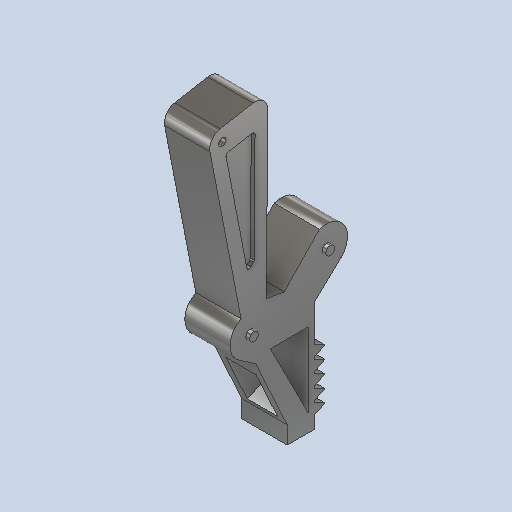
# Autodesk Inventor part: 8
Saved by Autodesk Inventor 2027.1 (Build 311270010, 270A)
## iProperties
Part Number: 8
Material: Allgemein
Document SubType Name: Modellieren
Designer: Asus
Appearance: Chrom - poliert
Author: Asus
Autodesk Inventor part; units mm, degrees
ref_plane "YZ-Ebene" through (0, 0, 0) normal (1, 0, 0) x (0, 1, 0)
ref_plane "XZ-Ebene" through (0, 0, 0) normal (0, 1, 0) x (-1, 0, 0)
ref_plane "XY-Ebene" through (0, 0, 0) normal (0, 0, 1) x (1, 0, 0)
sketch "Skizze1" plane through (0, 0, 0) normal (0, 0, 1) x (1, 0, 0)
  line L0 (0, 0) -> (0, 7)
  line L1 (0, 0) -> (11, 0)
  line L2 (11, 0) -> (11, 44)
  line L3 (0, 7) -> (-12.536, 34.2552)
  line L4 (11, 44) -> (21.3729, 53.8435)
  line L5 (-12.536, 34.2552) -> (-23.2368, 41.6372)
  line L6 (-23.2368, 41.6372) -> (-23.2368, 51.6372)
  line L7 (-23.2368, 51.6372) -> (-18.3337, 52.6169)
  line L8 (-18.3337, 52.6169) -> (-31.6903, 121.3308)
  line L9 (-31.6903, 121.3308) -> (-7.6903, 125.5627)
  line L10 (-7.6903, 125.5627) -> (-8.3099, 54.5654)
  line L11 (-8.3099, 54.5654) -> (-1.2087, 53.3771)
  line L12 (-1.2087, 53.3771) -> (12.8488, 67.8832)
  arc A0 (21.3729, 53.8435) -> (12.8488, 67.8832) centre (15.5884, 59.939) ccw
  dimension "d0" = 7
  dimension "d1" = 11
  dimension "d2" = 44
  dimension "d3" = 30
  dimension "d4" = 155.3
  dimension "d5" = 14.3
  dimension "d6" = 133.5
  dimension "d7" = 149.3
  dimension "d8" = 13
  dimension "d10" = 10
  dimension "d11" = 5
  dimension "d12" = 101.3
  dimension "d13" = 70
  dimension "d14" = 90.3
  dimension "d15" = 24
  dimension "d16" = 89
  dimension "d17" = 71
  dimension "d18" = 79.5
  dimension "d19" = 7.2
  dimension "d20" = 99
  dimension "d21" = 20.2
  dimension "d22" = 124.6
  constraints: 26 end point, 2 point on circle, 2 vertical, 1 centre point, 1 horizontal, 1 perpendicular, 1 tangent
  measures "d0" distance of L0.start L0.end
  measures "d1" distance of L0.start L1.end
  measures "d2" distance of L1.end L2.end
  measures "d3" distance of L0.end L3.end
  measures "d4" angle of L0 L3
  measures "d5" distance of L2.end L4.end
  measures "d6" angle of L2 L4
  measures "d7" angle of L3 L5
  measures "d8" distance of L3.end L5.end
  measures "d10" distance of L5.end L6.end
  measures "d11" distance of L6.end L7.end
  measures "d12" angle of L6 L7
  measures "d13" distance of L7.end L8.end
  measures "d14" angle of L7 L8
  measures "d15" horizontal distance of L8.end L9.end
  measures "d16" angle of L8 L9
  measures "d17" distance of L9.end L10.end
  measures "d18" angle of L10 L9
  measures "d19" distance of L10.end L11.end
  measures "d20" angle of L11 L10
  measures "d21" distance of L11.end L12.end
  measures "d22" angle of L12 L11
extrude "Extrusion1" add sketch "Skizze1" along normal mid plane 18
sketch "Skizze2" plane through (0, 0, 9) normal (0, 0, 1) x (1, 0, 0)
  line L0 (11, 44) -> (11, 0) construction
  line L1 (11, 0) -> (0, 0) construction
  line L2 (0, 0) -> (0, 7) construction
  line L3 (0, 7) -> (-12.536, 34.2552) construction
  line L4 (-12.536, 34.2552) -> (-23.2368, 41.6372) construction
  line L5 (-23.2368, 41.6372) -> (-23.2368, 51.6372) construction
  line L6 (-23.2368, 51.6372) -> (-18.3337, 52.6169) construction
  line L7 (-18.3337, 52.6169) -> (-31.6903, 121.3308) construction
  line L8 (-31.6903, 121.3308) -> (-7.6903, 125.5627) construction
  line L9 (-7.6903, 125.5627) -> (-8.3099, 54.5654) construction
  line L10 (-8.3099, 54.5654) -> (-1.2087, 53.3771) construction
  line L11 (-1.2087, 53.3771) -> (12.8488, 67.8832) construction
  arc A0 (21.3729, 53.8435) -> (12.8488, 67.8832) centre (15.5884, 59.939) ccw construction
  line L12 (21.3729, 53.8435) -> (11, 44) construction
  line L13 (-6.7, 36.5061) -> (8.3, 36.5061)
  line L14 (8.3, 36.5061) -> (8.3, 7)
  line L15 (8.3, 7) -> (-6.7, 36.5061)
  line L16 (0, 7) -> (11, 7) construction
  dimension "d25" = 2.7
  dimension "d26" = 15
  dimension "d27" = 33.1
  constraints: 8 end point, 2 point on line, 1 horizontal, 1 parallel, 1 perpendicular
  measures "d25" distance between parallel lines of L0 L14
  measures "d26" distance of L13.start L13.end
  measures "d27" distance of L14.end L13.start
extrude "Extrusion2" cut sketch "Skizze2" against normal through all
sketch "Skizze3" plane through (0, 0, 9) normal (0, 0, 1) x (1, 0, 0)
  line L0 (8.3, 7) -> (8.3, 36.5061) construction
  line L1 (8.3, 36.5061) -> (-6.7, 36.5061) construction
  line L2 (-6.7, 36.5061) -> (8.3, 7) construction
  line L3 (11, 44) -> (11, 0) construction
  line L4 (11, 0) -> (0, 0) construction
  line L5 (0, 0) -> (0, 7) construction
  line L6 (0, 7) -> (-12.536, 34.2552) construction
  line L7 (-12.536, 34.2552) -> (-23.2368, 41.6372) construction
  line L8 (-23.2368, 41.6372) -> (-23.2368, 51.6372) construction
  line L9 (-23.2368, 51.6372) -> (-18.3337, 52.6169) construction
  line L10 (-18.3337, 52.6169) -> (-31.6903, 121.3308) construction
  line L11 (-31.6903, 121.3308) -> (-7.6903, 125.5627) construction
  line L12 (-7.6903, 125.5627) -> (-8.3099, 54.5654) construction
  line L13 (-8.3099, 54.5654) -> (-1.2087, 53.3771) construction
  line L14 (-1.2087, 53.3771) -> (12.8488, 67.8832) construction
  arc A0 (21.3729, 53.8435) -> (12.8488, 67.8832) centre (15.5884, 59.939) ccw construction
  line L15 (21.3729, 53.8435) -> (11, 44) construction
  line L16 (11, 7) -> (15, 7) construction
  line L17 (11, 9) -> (11, 5)
  line L18 (11, 5) -> (15, 7)
  line L19 (11, 9) -> (15, 7)
  dimension "d33" = 4
  dimension "d34" = 7
  dimension "d35" = 4
  constraints: 8 end point, 1 horizontal, 1 midpoint, 1 point on line, 1 vertical
  measures "d33" distance of L17.start L17.end
  measures "d34" distance between parallel lines of L4 L16
  measures "d35" distance of L16.start L16.end
extrude "Extrusion3" add sketch "Skizze3" against normal blind 18
pattern_linear "Rechteckige Anordnung1" count 5 spacing 5 along (0, 1, 0) of "Extrusion3"
fillet "Rundung1" radius 8 2 edges at (-23.2368, 51.6372, 0) (-23.2368, 41.6372, 0)
fillet "Rundung2" radius 5 2 edges at (-31.6903, 121.3308, 0) (-7.6903, 125.5627, 0)
sketch "Skizze4" plane through (0, 0, 9) normal (0, 0, 1) x (1, 0, 0)
  arc A0 (-26.6796, 122.2144) -> (-30.7195, 116.3363) centre (-25.8114, 117.2903) ccw projected
  point P0 (0, 0)
  constraints: 1 coincident
hole "Bohrung1" at (-25.8114, 117.2903, 9) direction (0, 0, -1) diameter 3 end through all
sketch "Skizze5" plane through (0, 7, -9) normal (-0.9085082, -0.4178671, 0) x (0, 0, 1)
  line L0 (0, 0) -> (18, 0) construction
  line L1 (18, 30) -> (18, 0) construction
  line L2 (0, 30) -> (18, 30) construction
  line L3 (0, 0) -> (0, 30) construction
  line L4 (9, 30) -> (9, 0) construction
  line L5 (3, 22.5) -> (15, 22.5)
  line L6 (15, 22.5) -> (15, 2)
  line L7 (15, 2) -> (3, 2)
  line L8 (3, 2) -> (3, 22.5)
  line L9 (3, 22.5) -> (15, 2) construction
  line L10 (15, 22.5) -> (3, 2) construction
  point P0 (9, -6.3596)
  point P1 (9, 12.25)
  point P2 (9, 15)
  dimension "d50" = 12
  dimension "d51" = 7.5
  dimension "d52" = 2
  constraints: 14 end point, 5 midpoint, 2 parallel, 1 horizontal, 1 perpendicular, 1 vertical alignment
  measures "d50" distance of L5.start L5.end
  measures "d51" distance between parallel lines of L5 L2
  measures "d52" distance between parallel lines of L0 L7
extrude "Extrusion4" cut sketch "Skizze5" against normal up to surface surface through (8.3, 7, 9) normal (-0.891423, -0.4531722, 0)
sketch "Skizze6" plane through (0, 0, 9) normal (0, 0, 1) x (1, 0, 0)
  circle A0 centre (-25.8114, 117.2903) radius 1.5 construction
  line L0 (11, 14) -> (15, 12) construction
  line L1 (15, 12) -> (11, 10) construction
  line L2 (11, 10) -> (11, 9) construction
  line L3 (11, 9) -> (15, 7) construction
  line L4 (15, 7) -> (11, 5) construction
  line L5 (11, 5) -> (11, 0) construction
  line L6 (11, 0) -> (0, 0) construction
  line L7 (0, 0) -> (0, 7) construction
  line L8 (0, 7) -> (-12.536, 34.2552) construction
  line L9 (-12.536, 34.2552) -> (-19.2618, 38.895) construction
  arc A1 (-18.3337, 52.6169) -> (-19.2618, 38.895) centre (-14.719, 45.4801) ccw construction
  line L10 (-18.3337, 52.6169) -> (-30.7195, 116.3363) construction
  arc A2 (-26.6796, 122.2144) -> (-30.7195, 116.3363) centre (-25.8114, 117.2903) ccw construction
  line L11 (-26.6796, 122.2144) -> (-13.6109, 124.5187) construction
  arc A3 (-7.7428, 119.5511) -> (-13.6109, 124.5187) centre (-12.7426, 119.5947) ccw construction
  line L12 (-7.7428, 119.5511) -> (-8.3099, 54.5654) construction
  line L13 (-8.3099, 54.5654) -> (-1.2087, 53.3771) construction
  line L14 (-1.2087, 53.3771) -> (12.8488, 67.8832) construction
  arc A4 (21.3729, 53.8435) -> (12.8488, 67.8832) centre (15.5884, 59.939) ccw construction
  line L15 (21.3729, 53.8435) -> (11, 44) construction
  line L16 (11, 44) -> (11, 29) construction
  line L17 (11, 29) -> (15, 27) construction
  line L18 (15, 27) -> (11, 25) construction
  line L19 (11, 25) -> (11, 24) construction
  line L20 (11, 24) -> (15, 22) construction
  line L21 (15, 22) -> (11, 20) construction
  line L22 (11, 20) -> (11, 19) construction
  line L23 (11, 19) -> (15, 17) construction
  line L24 (15, 17) -> (11, 15) construction
  line L25 (11, 15) -> (11, 14) construction
  line L26 (8.3, 7) -> (8.3, 36.5061) construction
  line L27 (8.3, 36.5061) -> (-6.7, 36.5061) construction
  line L28 (-6.7, 36.5061) -> (8.3, 7) construction
  circle A5 centre (15.5884, 59.939) radius 1.75
  circle A6 centre (-14.719, 45.4801) radius 1.75
  dimension "d55" = 3.5
  dimension "d56" = 3.5
  constraints: 2 centre point, 2 coincident
  measures "d55" diameter of A5
  measures "d56" diameter of A6
extrude "Extrusion5" add sketch "Skizze6" along normal blind 1.5
sketch "Skizze7" plane through (0, 0, 9) normal (0, 0, 1) x (1, 0, 0)
  circle A0 centre (15.5884, 59.939) radius 1.75 construction
  circle A1 centre (-14.719, 45.4801) radius 1.75 construction
  circle A2 centre (-25.8114, 117.2903) radius 1.5 construction
  line L0 (11, 14) -> (15, 12) construction
  line L1 (15, 12) -> (11, 10) construction
  line L2 (11, 10) -> (11, 9) construction
  line L3 (11, 9) -> (15, 7) construction
  line L4 (15, 7) -> (11, 5) construction
  line L5 (11, 5) -> (11, 0) construction
  line L6 (11, 0) -> (0, 0) construction
  line L7 (0, 0) -> (0, 7) construction
  line L8 (0, 7) -> (-12.536, 34.2552) construction
  line L9 (-12.536, 34.2552) -> (-19.2618, 38.895) construction
  arc A3 (-18.3337, 52.6169) -> (-19.2618, 38.895) centre (-14.719, 45.4801) ccw construction
  line L10 (-18.3337, 52.6169) -> (-30.7195, 116.3363) construction
  arc A4 (-26.6796, 122.2144) -> (-30.7195, 116.3363) centre (-25.8114, 117.2903) ccw construction
  line L11 (-26.6796, 122.2144) -> (-13.6109, 124.5187) construction
  arc A5 (-7.7428, 119.5511) -> (-13.6109, 124.5187) centre (-12.7426, 119.5947) ccw construction
  line L12 (-7.7428, 119.5511) -> (-8.3099, 54.5654) construction
  line L13 (-8.3099, 54.5654) -> (-1.2087, 53.3771) construction
  line L14 (-1.2087, 53.3771) -> (12.8488, 67.8832) construction
  arc A6 (21.3729, 53.8435) -> (12.8488, 67.8832) centre (15.5884, 59.939) ccw construction
  line L15 (21.3729, 53.8435) -> (11, 44) construction
  line L16 (11, 44) -> (11, 29) construction
  line L17 (11, 29) -> (15, 27) construction
  line L18 (15, 27) -> (11, 25) construction
  line L19 (11, 25) -> (11, 24) construction
  line L20 (11, 24) -> (15, 22) construction
  line L21 (15, 22) -> (11, 20) construction
  line L22 (11, 20) -> (11, 19) construction
  line L23 (11, 19) -> (15, 17) construction
  line L24 (15, 17) -> (11, 15) construction
  line L25 (11, 15) -> (11, 14) construction
  line L26 (8.3, 7) -> (8.3, 36.5061) construction
  line L27 (8.3, 36.5061) -> (-6.7, 36.5061) construction
  line L28 (-6.7, 36.5061) -> (8.3, 7) construction
  line L29 (-23.5041, 112.62) -> (-13.9711, 114.301)
  line L30 (-24.312, 111.4444) -> (-16.0623, 69.0032)
  line L31 (-12.7975, 113.3074) -> (-13.1731, 70.2684)
  line L32 (-14.3142, 68.5517) -> (-13.4066, 69.6349)
  arc A7 (-23.5041, 112.62) -> (-24.312, 111.4444) centre (-23.3304, 111.6352) ccw
  arc A8 (-12.7975, 113.3074) -> (-13.9711, 114.301) centre (-13.7974, 113.3162) ccw
  arc A9 (-16.0623, 69.0032) -> (-14.3142, 68.5517) centre (-15.0807, 69.194) ccw
  arc A10 (-13.4066, 69.6349) -> (-13.1731, 70.2684) centre (-14.173, 70.2771) ccw
  point P0 (-24.5062, 112.4433)
  point P1 (-12.787, 114.5098)
  point P2 (-15.6619, 66.9433)
  point P3 (-13.1762, 69.9098)
  dimension "d59" = 11.9
  dimension "d60" = 10
  dimension "d61" = 89
  dimension "d62" = 79.5
  dimension "d63" = 45.5
  dimension "d64" = 44.6
  dimension "d65" = 5
  dimension "d66" = 1
  dimension "d67" = 1
  constraints: 8 end point, 8 point on circle, 8 point on line, 8 tangent, 4 centre point, 2 equal radius, 1 parallel
  measures "d59" distance of point (-24.506, 112.443) point (-12.787, 114.51)
  measures "d60" distance between parallel lines of L29 L11
  measures "d61" angle of L30 L29
  measures "d62" angle of L31 L29
  measures "d63" vertical distance of point (-24.506, 112.443) point (-15.662, 66.943)
  measures "d64" vertical distance of point (-12.787, 114.51) point (-13.176, 69.91)
  measures "d65" distance from line of L12 point (-13.176, 69.91)
  measures "d66" radius of A7
  measures "d67" radius of A10
extrude "Extrusion6" add sketch "Skizze7" along normal blind 1.5
ref_plane "Arbeitsebene1" through (0, 0, 0) normal (0, 0, 1) x (1, 0, 0)
mirror "Spiegeln1" about plane through (0, 0, 0) normal (0, 0, 1) of "Extrusion6", "Extrusion5", "Bohrung1"
sketch "Skizze8" plane through (0, 0, 10.5) normal (0, 0, 1) x (1, 0, 0)
  arc A0 (-16.0623, 69.0032) -> (-14.3142, 68.5517) centre (-15.0807, 69.194) ccw projected
  line L0 (-14.3142, 68.5517) -> (-13.4066, 69.6349) projected
  arc A1 (-13.4066, 69.6349) -> (-13.1731, 70.2684) centre (-14.173, 70.2771) ccw projected
  line L1 (-13.1731, 70.2684) -> (-12.7975, 113.3074) projected
  arc A2 (-12.7975, 113.3074) -> (-13.9711, 114.301) centre (-13.7974, 113.3162) ccw projected
  line L2 (-13.9711, 114.301) -> (-23.5041, 112.62) projected
  arc A3 (-23.5041, 112.62) -> (-24.312, 111.4444) centre (-23.3304, 111.6352) ccw projected
  line L3 (-24.312, 111.4444) -> (-16.0623, 69.0032) projected
  point P0 (0, 0)
extrude "Extrusion7" cut sketch "Skizze8" against normal blind 3
mirror "Spiegeln2" about plane through (0, 0, 0) normal (0, 0, 1) of "Extrusion7"
